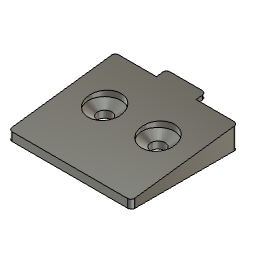
HamptonBayFanRemoteWallClip v2 (Autodesk Fusion 360 design; units mm, degrees)
Autodesk Fusion 360 part; units mm, degrees
sketch "Sketch1" plane through (0, 0, 0) normal (0, 0, 1) x (1, 0, 0)
  line L0 (0, 0) -> (35.2, 0)
  line L1 (35.2, 0) -> (35.2, -30.5)
  line L2 (35.2, -30.5) -> (0, -30.5)
  line L3 (0, -30.5) -> (0, 0)
  line L4 (17.6, 0) -> (17.6, -30.5) construction
  line L5 (0, -12.9) -> (35.2, -12.9) construction
  circle A0 centre (9.95, -12.9) radius 2.05
  circle A1 centre (25.25, -12.9) radius 2.05
  circle A2 centre (9.95, -12.9) radius 4.7
  circle A3 centre (25.25, -12.9) radius 4.7
  line L6 (23.3, 0) -> (11.9, 0)
  line L7 (11.9, 0) -> (11.9, 2.8)
  line L8 (11.9, 2.8) -> (23.3, 2.8)
  line L9 (23.3, 2.8) -> (23.3, 0)
  point P0 (9.95, -12.9)
  point P1 (25.25, -12.9)
  dimension "d1" = 35.2
  dimension "d2" = 30.5
  dimension "d3" = 17.6
  dimension "d4" = 15.3
  dimension "d5" = 4.1
  dimension "d6" = 4.1
  dimension "d7" = 9.4
  dimension "d8" = 9.4
  dimension "d16" = 11.4
  dimension "d17" = 2.8
  constraint horizontal L0
  constraint vertical L1
  constraint horizontal L2
  constraint vertical L3
  constraint coincident L0.start L3.end
  constraint midpoint L0 L4.start
  constraint midpoint L2 L4.end
  constraint coincident L3 L5.start
  constraint coincident L1 L5.end
  constraint perpendicular L1 L5
  constraint coincident L5 P0
  constraint coincident L5 P1
  constraint symmetric L4 P0 P1
  constraint coincident P0 A0.centre
  constraint coincident P1 A1.centre
  constraint concentric A0 A2
  constraint concentric A1 A3
  constraint horizontal L6
  constraint vertical L7
  constraint horizontal L8
  constraint vertical L9
  constraint coincident L0 L6.start
  constraint symmetric L4 L7 L9
  measures "d1" distance of L0.start L0.end
  measures "d2" distance of L0.start L2.end
  measures "d3" distance of L2 L5
  measures "d4" distance of P0 P1
  measures "d5" diameter of A0
  measures "d6" diameter of A1
  measures "d7" diameter of A2
  measures "d8" diameter of A3
  measures "d16" distance of L6.start L6.end
  measures "d17" distance of L6.start L8.end
extrude "Extrude1" add sketch "Sketch1" along normal blind 6.3 contours L0 L1 L2 L3 L6 | A2 | A3
sketch "Sketch2" plane through (0, 0, 0) normal (-1, 0, 0) x (0, -1, 0)
  line L0 (0, 0) -> (30.5, 0)
  line L1 (30.5, 0) -> (30.5, 6.3)
  line L2 (30.5, 6.3) -> (0, 6.3)
  line L3 (0, 6.3) -> (0, 0)
  line L4 (0, 6.3) -> (30.5, 2.4)
  line L5 (30.5, 2.4) -> (30.5, 0)
  line L6 (30.5, 0) -> (0, 0)
  line L7 (0, 0) -> (0, 6.3)
  line L8 (0, 6.3) -> (-2.7774, 6.6551)
  line L9 (-2.7774, 6.6551) -> (-2.9296, 5.4648) construction
  line L10 (-2.9296, 5.4648) -> (0, 5.0902)
  line L11 (-2.7774, 6.6551) -> (-2.7774, 5.4454)
  dimension "d11" = 2.4
  dimension "d12" = 2.8
  dimension "d13" = 1.2
  constraint coincident L2.end L3.start
  constraint coincident L1 L4.end
  constraint coincident L0.end L1.start
  constraint coincident L0.start L3.end
  constraint collinear L4 L8
  constraint perpendicular L8 L9
  constraint coincident L7 L10.end
  constraint perpendicular L9 L10
  constraint coincident L10 L11.end
  constraint vertical L11
  measures "d11" distance of L0 L4.end
  measures "d12" distance of L2.end L8.end
  measures "d13" distance of L8.end L9.end
extrude "Extrude2" cut sketch "Sketch2" against normal up to surface (35.2 mm away) contours L1 L2 L4
extrude "Extrude3" add sketch "Sketch2" against normal up to surface (11.4 mm away) from surface at -11.9 contours L3 L7 L8 L10 L11
extrude "Extrude4" cut sketch "Sketch1" along normal blind 4 from surface at 2 contours A2 | A3
chamfer "Chamfer1" distance 2.65 distance2 1.5 2 edges at (5.5681, -14.5996, 2) (20.8681, -14.5996, 2) measured on face at (13.7492, -13.1335, 2) measured on face at (29.0492, -13.1335, 2)
fillet "Fillet1" radius 1 6 edges at (0, -30.5, 1.2) (35.2, -30.5, 1.2) (35.2, 0, 3.15) (0, 0, 3.15) (23.3, 2.7774, 6.0503) (11.9, 2.7774, 6.0503)
